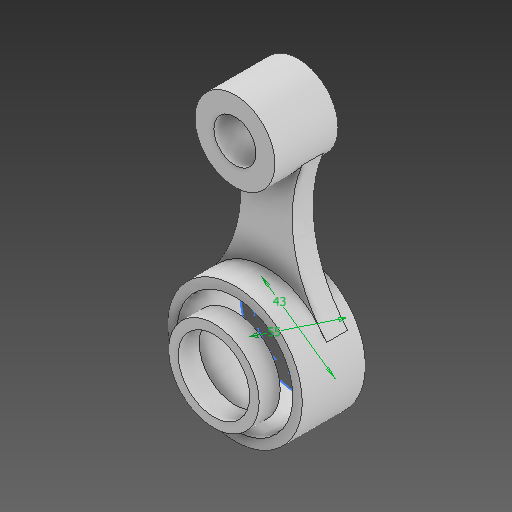
# Autodesk Inventor part: Hoja de Trabajo en clase lunes 17
Saved by Autodesk Inventor 2026.1 (Build 301233020, 233B)
## iProperties
Created: 2026-08-17
Part Number: Hoja de Trabajo en clase lunes 17
Material: Generic
Document SubType Name: Modeling
Designer: YmCris
Density: 1 g/cm^3
Appearance: Default
Author: YmCris
Autodesk Inventor part; units mm, degrees
ref_plane "YZ Plane" through (0, 0, 0) normal (1, 0, 0) x (0, 1, 0)
ref_plane "XZ Plane" through (0, 0, 0) normal (0, 1, 0) x (-1, 0, 0)
ref_plane "XY Plane" through (0, 0, 0) normal (0, 0, 1) x (1, 0, 0)
sketch "Sketch1" plane through (0, 0, 0) normal (0, 0, 1) x (1, 0, 0)
  circle A0 centre (0, 43.419) radius 19.9006
  circle A1 centre (0, 43.419) radius 10
  circle A2 centre (0, -65.244) radius 42.3524
  circle A3 centre (0, -65.244) radius 27.5
  arc A4 (19, 37.5) -> (32, -37.5) centre (76.1979, 8.7876) ccw
  arc A5 (-32, -37.5) -> (-19, 37.5) centre (-76.1979, 8.7876) ccw
  point P0 (-16.9536, 32.9973)
  point P1 (-28.6551, -34.0573)
  point P2 (28.6551, -34.0573)
  point P3 (16.9536, 32.9973)
  constraints: 4 centre point, 4 point on circle, 2 coincident, 6 other
extrude "Extrusion1" add sketch "Sketch1" along normal blind 10 contours A0 A4 A2 A5
sketch "Sketch2" plane through (0, 0, 10) normal (0, 0, 1) x (1, 0, 0)
  circle A0 centre (0, 41.9659) radius 19
  point P0 (0, 0)
  constraints: 1 centre point
extrude "Extrusion2" add sketch "Sketch2" along normal mid plane 30
sketch "Sketch3" plane through (0, 41.9659, 25) normal (0, 0, 1) x (1, 0, 0)
  circle A0 centre (0, 0) radius 10
  point P0 (0, -41.9659)
  dimension "d16" = 20
  constraints: 1 centre point
  measures "d16" diameter of A0
extrude "Extrusion3" cut sketch "Sketch3" against normal blind 30
sketch "Sketch4" plane through (0, 0, 10) normal (0, 0, 1) x (1, 0, 0)
  circle A0 centre (0, -49.665) radius 32
  point P0 (0, 0)
  dimension "d19" = 64
  constraints: 1 centre point
  measures "d19" diameter of A0
extrude "Extrusion4" add sketch "Sketch4" along normal mid plane 30
sketch "Sketch5" plane through (0, -49.665, 25) normal (0, 0, 1) x (1, 0, 0)
  circle A0 centre (0, 0) radius 27.5
  point P0 (0, 49.665)
  dimension "d22" = 55
  constraints: 1 centre point
  measures "d22" diameter of A0
sketch "Sketch6" plane through (0, -49.665, 25) normal (0, 0, 1) x (1, 0, 0)
  circle A0 centre (0, 0) radius 17
  point P0 (0, 49.665)
  dimension "d23" = 34
  constraints: 1 centre point
  measures "d23" diameter of A0
extrude "Extrusion5" add sketch "Sketch6" along normal blind 10
sketch "Sketch7" plane through (0, -49.665, 25) normal (0, 0, 1) x (1, 0, 0)
  circle A0 centre (0, 0) radius 21.5
  point P0 (0, 49.665)
  constraints: 1 centre point
extrude "Extrusion6" add sketch "Sketch7" along normal blind 10
sketch "Sketch8" plane through (0, -49.665, 35) normal (0, 0, 1) x (1, 0, 0)
  circle A0 centre (0, 0) radius 17
  point P0 (0, 49.665)
  dimension "d29" = 34
  constraints: 1 centre point
  measures "d29" diameter of A0
extrude "Extrusion7" cut sketch "Sketch8" against normal blind 45
sketch "Sketch9" plane through (0, -49.665, -5) normal (0, 0, -1) x (-1, 0, 0)
  circle A0 centre (0, 0) radius 27.5
  point P0 (0, 49.665)
  dimension "d32" = 55
  constraints: 1 centre point
  measures "d32" diameter of A0
sketch "Sketch10" plane through (0, -49.665, -5) normal (0, 0, -1) x (-1, 0, 0)
  circle A0 centre (0, 0) radius 21.5
  point P0 (0, 49.665)
  dimension "d33" = 43
  constraints: 1 centre point
  measures "d33" diameter of A0
extrude "Extrusion8" cut sketch "Sketch5" against normal blind 30
body "Solid1"
